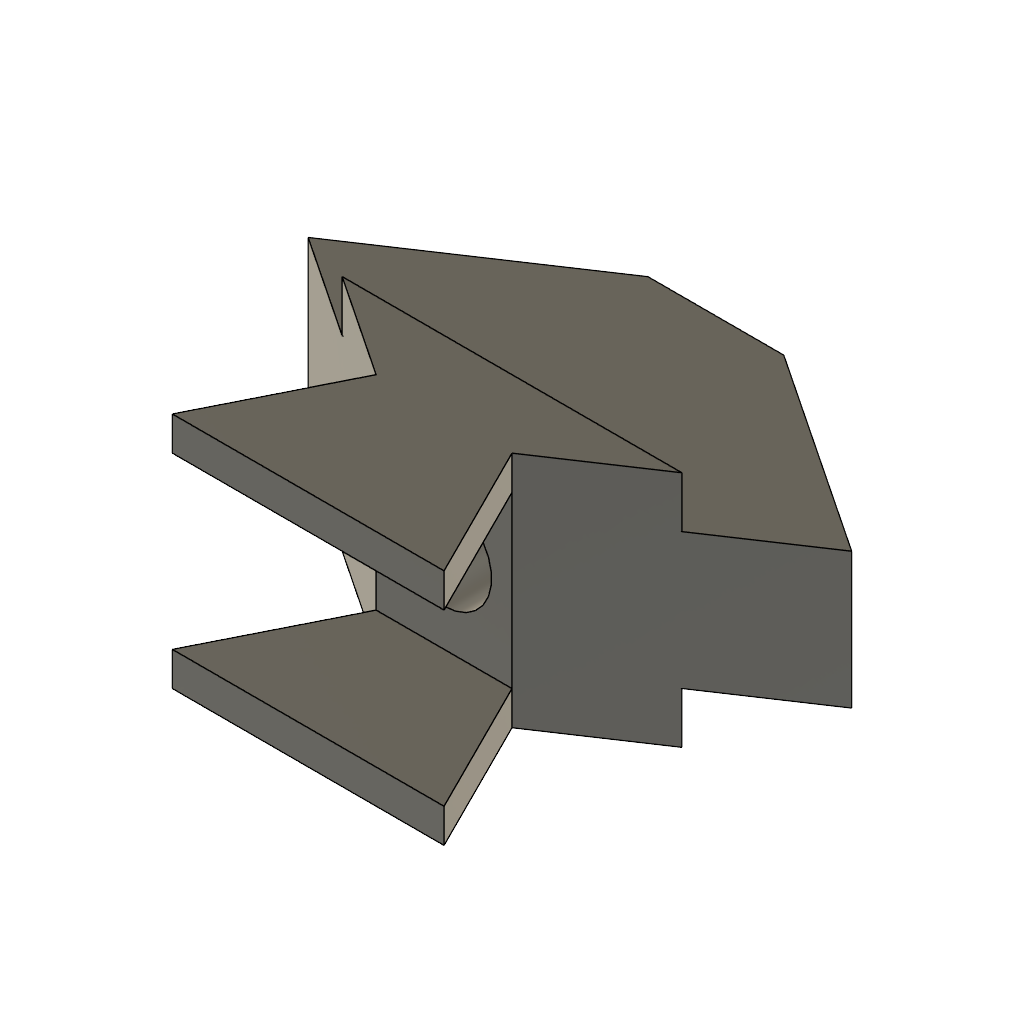
pieza_5 (Autodesk Fusion 360 design; units mm, degrees)
part number: 2026-11-08-09-54-45-929
Autodesk Fusion 360 part; units mm, degrees
sketch "Boceto1" plane through (0, 0, 0) normal (0, 0, 1) x (1, 0, 0)
  line L0 (40, 0) -> (25, 10)
  line L1 (25, 10) -> (15, 10)
  line L2 (15, 10) -> (0, 0)
  line L3 (0, 0) -> (15, -10)
  line L4 (15, -10) -> (10, -20)
  line L5 (10, -20) -> (30, -20)
  line L6 (30, -20) -> (25, -10)
  line L7 (25, -10) -> (40, 0)
  line L8 (7.5, -5) -> (32.5, -5)
  constraint coincident L2.end L3.start
  constraint parallel L0 L3
  constraint midpoint L3 L8.start
  constraint midpoint L7 L8.end
  constraint parallel L5 L8
extrude "Extruir1" add sketch "Boceto1" along normal blind 2.5 contours L3 L4 L5 L6 L7 L8 makes body 1
copy_body "CopiarPegarCuerpos1" bodies 1 makes body 2
move_body "Desplazar1" bodies 2 to x (1, 0, 0) y (0, 1, 0) z (0, 0, 1) at (0, 0, 15)
sketch "Boceto2" plane through (0, 0, 0) normal (0, 0, 1) x (1, 0, 0)
  line L0 (15, 15) -> (25, 15)
  line L1 (25, 15) -> (40, 5)
  line L2 (40, 5) -> (32.5, 0)
  line L3 (15, 15) -> (0, 5)
  line L4 (0, 5) -> (7.5, 0)
  line L5 (7.5, 0) -> (32.5, 0)
  constraint parallel L1 L4
sketch "Boceto3" plane through (0, 0, 0) normal (0, 0, 1) x (1, 0, 0)
  line L0 (37.5, -5) -> (62.5, -5)
  line L1 (44.9927, -10.0189) -> (54.758, -10.0189)
  line L2 (37.5, -5) -> (44.9927, -10.0189)
  line L3 (54.758, -10.0189) -> (62.5, -5)
  line L4 (7.5, -5) -> (32.5, -5)
  line L5 (32.5, -5) -> (25, -10)
  line L6 (25, -10) -> (15, -10)
  line L7 (15, -10) -> (7.5, -5)
  constraint horizontal L0
  constraint parallel L0 L1
  constraint horizontal L4
  constraint parallel L4 L6
sketch "Boceto4" plane through (0, 0, 2.5) normal (0, 0, 1) x (-1, 0, 0)
  line L0 (-15, 10) -> (-10, 20)
  line L1 (-10, 20) -> (-30, 20)
  line L2 (-30, 20) -> (-25, 10)
  line L3 (-25, 10) -> (-32.5, 5)
  line L4 (-32.5, 5) -> (-7.5, 5)
  line L5 (-7.5, 5) -> (-15, 10)
  line L6 (-7.5, 5) -> (-32.5, 5)
  line L7 (-25, 10) -> (-15, 10)
  constraint coincident L4.end L5.start
  constraint coincident L3.end L4.start
  constraint coincident L2.end L3.start
  constraint coincident L0.start L5.end
extrude "Extruir2" add sketch "Boceto4" along normal blind 12.5 contours L3 L4 L5 L6 L7 bodies 1 2
extrude "Extruir3" add sketch "Boceto2" along normal blind 10 separate body makes body 3
move_body "Desplazar2" bodies 3 to x (1, 0, 0) y (0, 1, 0) z (0, 0, 1) at (0, -5, 3.75)
hole "Agujero1" at (20, 10, 8.75) direction (0, -1, 0) diameter 7 depth 8 tip angle 180 bodies 3
hole "Agujero2" at (20, -10, 8.75) direction (0, 1, 0) diameter 7 depth 8 tip angle 180 bodies 3 1
combine "Combinar1" operation add target body 3 tool bodies 1
